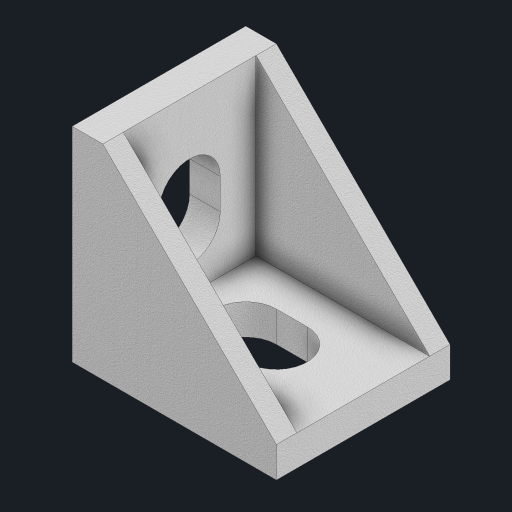
# Autodesk Inventor part: Cantoneira em Alumínio 20X20X17
Saved by Autodesk Inventor 2024.3 (Build 283343000, 343)
## iProperties
Created: 2025-07-09
Part Number: Cantoneira em Alumínio 20X20X17
Material: Alumínio
Document SubType Name: Modeling
Designer: Cliente
Density: 2.7 g/cm^3
Appearance: Acetinado
Mass: 5.97516 g
Surface Area: 21.2782 cm^2
Volume: 2.21302 cm^3
Author: Cliente
Autodesk Inventor part; units mm, degrees
ref_plane "YZ Plane" through (0, 0, 0) normal (1, 0, 0) x (0, 1, 0)
ref_plane "XZ Plane" through (0, 0, 0) normal (0, 1, 0) x (-1, 0, 0)
ref_plane "XY Plane" through (0, 0, 0) normal (0, 0, 1) x (1, 0, 0)
sketch "Esboço1" plane through (0, 0, 0) normal (0, 0, 1) x (1, 0, 0)
  line L0 (0, 0) -> (20, 0)
  line L1 (20, 0) -> (20, 3)
  line L2 (0, 0) -> (0, 20)
  line L3 (0, 20) -> (3, 20)
  line L4 (3, 20) -> (20, 3)
  dimension "d0" = 20
  dimension "d1" = 3
  dimension "d2" = 20
  dimension "d3" = 3
  constraints: 10 end point, 2 perpendicular, 1 coincident, 1 horizontal, 1 vertical
  measures "d0" distance of L0.start L0.end
  measures "d1" distance of L0.end L1.end
  measures "d2" distance of L0.start L2.end
  measures "d3" distance of L2.end L3.end
extrude "Extrusão1" add sketch "Esboço1" along normal mid plane 17
sketch "Esboço2" plane through (0, 20, 8.5) normal (0, 1, 0) x (1, 0, 0)
  line L0 (3, 17) -> (3, 0) projected
  line L1 (20, 0) -> (3, 0) projected
  line L2 (20, 17) -> (20, 0) projected
  line L3 (3, 17) -> (20, 17) projected
  line L4 (3, 0) -> (3, 2)
  line L5 (3, 2) -> (20, 2)
  line L6 (3, 17) -> (3, 15)
  line L7 (3, 15) -> (20, 15)
  point P0 (0, 8.5)
  dimension "d6" = 2
  dimension "d7" = 2
  constraints: 8 end point, 4 point on line, 2 perpendicular
  measures "d6" distance of L0.end L4.end
  measures "d7" distance of L0.start L6.end
extrude "Extrusão2" cut sketch "Esboço2" against normal blind 17 contours L7 L2 L5 L0
sketch "Esboço3" plane through (0, 0, 8.5) normal (0, -1, 0) x (1, 0, 0)
  line L0 (20, -17) -> (20, 0) projected
  line L1 (0, 0) -> (20, 0) projected
  line L2 (0, 0) -> (0, -17) projected
  line L3 (20, -17) -> (0, -17) projected
  line L4 (8.5, -8.5) -> (11.5, -8.5) construction
  line L5 (20, -15) -> (20, -2) projected
  line L6 (8.5, -11.5) -> (11.5, -11.5)
  line L7 (11.5, -5.5) -> (8.5, -5.5)
  arc A0 (8.5, -5.5) -> (8.5, -11.5) centre (8.5, -8.5) ccw
  arc A1 (11.5, -11.5) -> (11.5, -5.5) centre (11.5, -8.5) ccw
  line L8 (2.5, -8.5) -> (17.5, -8.5)
  line L9 (2.5, -10.8) -> (2.5, -10.8)
  line L10 (1.75, -10.05) -> (1.75, -6.95)
  line L11 (2.5, -6.2) -> (2.5, -6.2)
  line L12 (3.25, -6.95) -> (3.25, -10.05)
  line L13 (3.25, -10.8) -> (1.75, -6.2) construction
  line L14 (1.75, -10.8) -> (3.25, -6.2) construction
  line L15 (17.5, -10.8) -> (17.5, -10.8)
  line L16 (16.75, -10.05) -> (16.75, -6.95)
  line L17 (17.5, -6.2) -> (17.5, -6.2)
  line L18 (18.25, -6.95) -> (18.25, -10.05)
  line L19 (18.25, -10.8) -> (16.75, -6.2) construction
  line L20 (16.75, -10.8) -> (18.25, -6.2) construction
  arc A2 (2.5, -6.2) -> (1.75, -6.95) centre (2.5, -6.95) ccw
  arc A3 (1.75, -10.05) -> (2.5, -10.8) centre (2.5, -10.05) ccw
  arc A4 (2.5, -10.8) -> (3.25, -10.05) centre (2.5, -10.05) ccw
  arc A5 (3.25, -6.95) -> (2.5, -6.2) centre (2.5, -6.95) ccw
  arc A6 (18.25, -6.95) -> (17.5, -6.2) centre (17.5, -6.95) ccw
  arc A7 (17.5, -10.8) -> (18.25, -10.05) centre (17.5, -10.05) ccw
  arc A8 (16.75, -10.05) -> (17.5, -10.8) centre (17.5, -10.05) ccw
  arc A9 (17.5, -6.2) -> (16.75, -6.95) centre (17.5, -6.95) ccw
  point P0 (0, -8.5)
  point P1 (10, -8.5)
  point P2 (0, -8.5)
  point P3 (10, 0)
  point P4 (10, -8.5)
  dimension "d10" = 1.5
  dimension "d11" = 6
  dimension "d12" = 15
  dimension "d13" = 1.5
  dimension "d14" = 4.6
  dimension "d15" = 1.5
  dimension "d16" = 4.6
  dimension "d17" = 0.75
  constraints: 34 end point, 20 point on circle, 20 tangent, 16 point on line, 10 centre point, 8 midpoint, 7 equal radius, 5 parallel, 3 horizontal, 3 perpendicular, 1 coincident, 1 horizontal alignment, 1 vertical alignment
  measures "d10" distance of point (10, -8.5) L4.end
  measures "d11" diameter of A1
  measures "d12" distance of L8.start L8.end
  measures "d13" distance of L13.end L14.end
  measures "d14" distance of L14.start L13.end
  measures "d15" distance of L19.end L20.end
  measures "d16" distance of L20.start L19.end
  measures "d17" radius of A2
extrude "Extrusão3" cut sketch "Esboço3" against normal through all contours A0 L8 A1 L6 | A0 L7 A1 L8
extrude "Extrusão4" add sketch "Esboço3" along normal blind 1 contours L12 A4 A3 L10 A2 A5 | L16 A9 A6 L18 A7 A8
sketch "Esboço4" plane through (0, 0, 8.5) normal (-1, 0, 0) x (0, 0, 1)
  line L0 (0, 0) -> (-17, 0) projected
  line L1 (0, 20) -> (0, 0) projected
  line L2 (-17, 20) -> (0, 20) projected
  line L3 (-17, 0) -> (-17, 20) projected
  line L4 (-8.5, 11.5) -> (-8.5, 8.5) construction
  line L5 (-11.5, 11.5) -> (-11.5, 8.5)
  line L6 (-5.5, 8.5) -> (-5.5, 11.5)
  arc A0 (-5.5, 11.5) -> (-11.5, 11.5) centre (-8.5, 11.5) ccw
  arc A1 (-11.5, 8.5) -> (-5.5, 8.5) centre (-8.5, 8.5) ccw
  line L7 (-6.2, 17.5) -> (-10.8, 17.5) construction
  line L8 (-6.95, 18.25) -> (-10.05, 18.25)
  line L9 (-10.05, 16.75) -> (-6.95, 16.75)
  arc A2 (-6.95, 16.75) -> (-6.95, 18.25) centre (-6.95, 17.5) ccw
  arc A3 (-10.05, 18.25) -> (-10.05, 16.75) centre (-10.05, 17.5) ccw
  line L10 (-10.8, 2.5) -> (-6.2, 2.5) construction
  line L11 (-10.05, 1.75) -> (-6.95, 1.75)
  line L12 (-6.95, 3.25) -> (-10.05, 3.25)
  arc A4 (-10.05, 3.25) -> (-10.05, 1.75) centre (-10.05, 2.5) ccw
  arc A5 (-6.95, 1.75) -> (-6.95, 3.25) centre (-6.95, 2.5) ccw
  line L13 (0, 0) -> (-17, 0) projected
  line L14 (-8.5, 17.5) -> (-8.5, 2.5)
  point P0 (-8.5, 0)
  point P1 (-8.5, 10)
  point P2 (0, 10)
  point P3 (-8.5, 0)
  point P4 (-8.5, 17.5)
  point P5 (-8.5, 2.5)
  point P6 (-8.5, 0)
  point P7 (-8.5, 10)
  dimension "d22" = 1.5
  dimension "d23" = 6
  dimension "d24" = 4.6
  dimension "d25" = 1.5
  dimension "d26" = 4.6
  dimension "d27" = 1.5
  dimension "d28" = 15
  constraints: 26 end point, 16 point on circle, 12 tangent, 7 midpoint, 6 centre point, 4 parallel, 4 point on line, 3 coincident, 3 vertical alignment, 2 vertical, 1 horizontal, 1 horizontal alignment
  measures "d22" distance of point (-8.5, 10) L4.end
  measures "d23" diameter of A1
  measures "d24" distance of L7.start L7.end
  measures "d25" diameter of A3
  measures "d26" distance of L10.start L10.end
  measures "d27" diameter of A5
  measures "d28" distance of L14.start L14.end
extrude "Extrusão5" cut sketch "Esboço4" against normal through all contours A0 L14 A1 L5 | A0 L6 A1 L14
extrude "Extrusão6" add sketch "Esboço4" along normal blind 1 contours L9 A3 L8 A2 | L12 A5 L11 A4
